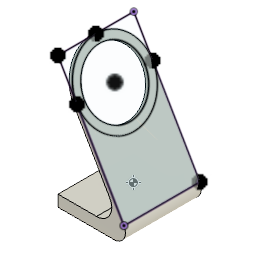
RCM Test (Autodesk Fusion 360 design; units mm, degrees)
part number: 2026-08-20-15-12-21-887
Autodesk Fusion 360 part; units mm, degrees
sketch "Sketch1" plane through (0, 0, 0) normal (0, 1, 0) x (1, 0, 0)
  line L0 (24.0192, 0) -> (-50, 0)
  line L1 (37.0096, -22.5) -> (-50, -173.2051)
  line L2 (50, 0) -> (250, 0) construction
  arc A0 (37.0096, -22.5) -> (24.0192, 0) centre (24.0192, -15) ccw
  line L3 (18.2457, -45) -> (-54.3301, -170.7051)
  line L4 (0.9252, -15) -> (-50, -15)
  arc A1 (18.2457, -45) -> (0.9252, -15) centre (0.9252, -35) ccw
  line L5 (-50, -15) -> (-50, 0)
  line L6 (-54.3301, -170.7051) -> (-50, -173.2051)
  dimension "d1" = 100
  dimension "d2" = 120
  dimension "d20" = 20
  constraint horizontal L0
  constraint horizontal L2
  constraint coincident L0 origin
  constraint coincident L2.start L1
  constraint coincident L2.start L0
  constraint tangent L1 A0
  constraint tangent L0 A0
  constraint tangent L3 A1
  constraint tangent L4 A1
  constraint perpendicular L0 L5
  constraint perpendicular L1 L6
  measures "d1" distance of L2.start L0.end
  measures "d2" angle of L1 L2
  measures "d20" radius of A1
extrude "Extrude1" add sketch "Sketch1" along normal blind 50 and the other way blind 50
sketch "Sketch2" plane through (37.5, 0, 21.6506) normal (0.866025, 0, 0.5) x (0, 1, 0)
  line L0 (-50, 0.9808) -> (50, 0.9808)
  line L1 (50, 0.9808) -> (50, 175)
  line L2 (-50, 175) -> (-50, 0.9808)
  line L3 (-50, 175) -> (50, 175)
  line L4 (50, 175) -> (50, 0.9808)
  line L5 (50, 0.9808) -> (-50, 0.9808)
  line L6 (-50, 0.9808) -> (-50, 175)
  circle A0 centre (0, 125) radius 50
  circle A1 centre (0, 125) radius 40
  line L7 (50, 175) -> (-50, 175)
  point P0 (0, 175)
  point P1 (-50, 125)
  point P2 (50, 125)
  dimension "d10" = 50
  dimension "d11" = 50
  dimension "d12" = 50
  dimension "d13" = -10
  constraint horizontal L3
  constraint vertical L4
  constraint horizontal L5
  constraint vertical L6
  constraint coincident L0.end L1.start
  constraint coincident L2.start L3.start
  constraint midpoint L3 P0
  constraint coincident L2 P1
  constraint coincident L4 P2
  constraint coincident P1 A0
  constraint coincident P0 A0
  constraint coincident P2 A0
  measures "d10" distance of L2.start P0
  measures "d11" distance of L2.start P1
  measures "d12" distance of L1.end P2
extrude "Extrude2" cut sketch "Sketch2" against normal blind 5 contours L2 L3 L6 A0 L7 | L1 L3 L4 A0 L7
extrude "Extrude3" cut sketch "Sketch2" against normal blind 5 contours A1
equation "d2 = 180 deg - 60 deg"
